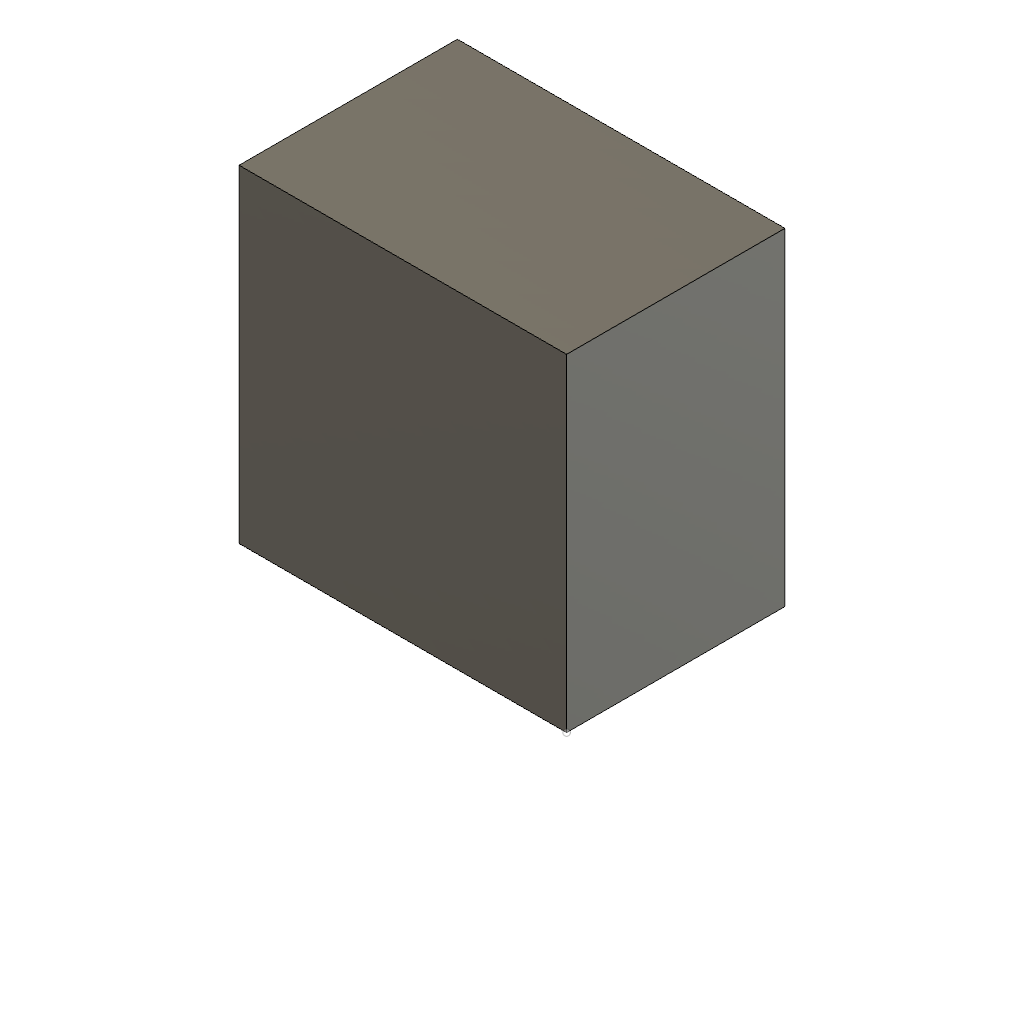
scale_construction_point (Autodesk Fusion 360 design; units mm, degrees)
part number: 2026-10-20-23-40-29-727
Autodesk Fusion 360 part; units mm, degrees
sketch "InputSourceSketch1" plane through (0, 0, 0) normal (0, 0, 1) x (1, 0, 0)
  line L0 (10, 10) -> (40, 10)
  line L1 (40, 10) -> (40, 40)
  line L2 (40, 40) -> (10, 40)
  line L3 (10, 40) -> (10, 10)
extrude "InputSourceExtrude1" add sketch "InputSourceSketch1" along normal blind 20
sketch "ReferencePointSketch" plane through (0, 0, 0) normal (0, 0, 1) x (1, 0, 0)
  point P0 (20, -10)
scale "ProbeScaleShellInput" factor 1.3 about (20, -10, 0) bodies 1
named bodies: "InputBody1"
